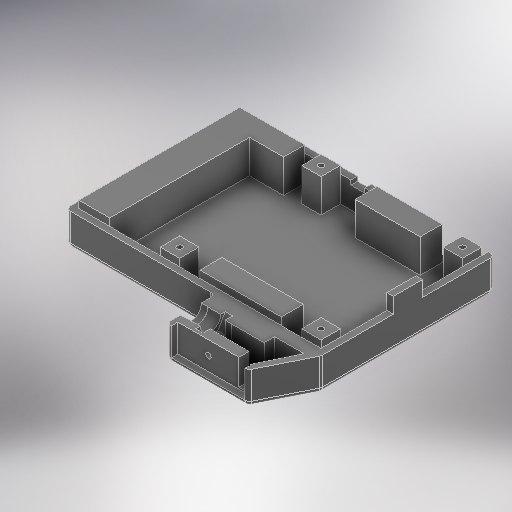
# Autodesk Inventor part: back_casing
Saved by Autodesk Inventor 2027 (Build 310192060, 192F)
## iProperties
Created: 2026-09-11
Part Number: back_casing
Material: Generic
Document SubType Name: Modeling
Designer: Aiden
Density: 1 g/cm^3
Appearance: Smooth - Black
Author: Aiden
Autodesk Inventor part; units mm, degrees
ref_plane "YZ Plane" through (0, 0, 0) normal (1, 0, 0) x (0, 1, 0)
ref_plane "XZ Plane" through (0, 0, 0) normal (0, 1, 0) x (-1, 0, 0)
ref_plane "XY Plane" through (0, 0, 0) normal (0, 0, 1) x (1, 0, 0)
sketch "Sketch1" plane through (0, 0, 0) normal (0, 1, 0) x (-1, 0, 0)
  line L0 (0, 0) -> (54.318, 0)
  line L1 (54.318, 0) -> (54.318, -54.318)
  line L2 (54.318, -54.318) -> (0, -54.318)
  line L3 (0, -54.318) -> (0, 0)
  line L4 (52.286, -52.286) -> (52.286, -54.318) construction
  line L5 (2.032, -2.032) -> (2.032, 0) construction
  line L6 (2.032, -52.286) -> (0, -52.286) construction
  line L7 (54.318, 0) -> (79.718, 0)
  line L8 (79.718, 0) -> (79.718, -54.318)
  line L9 (79.718, -54.318) -> (54.318, -54.318)
  line L10 (54.318, -54.318) -> (54.318, 0)
  dimension "d0" = 54.318
  dimension "d1" = 54.318
  dimension "d8" = 25.4
  constraints: 22 end point, 6 perpendicular, 4 parallel, 3 point on line, 2 horizontal
  measures "d0" distance of L0.end L1.end
  measures "d1" distance of L1.end L2.end
  measures "d8" distance of L8.end L9.end
extrude "Extrusion1" add sketch "Sketch1" along normal blind 10.16
sketch "Sketch3" plane through (0, 10.16, 0) normal (0, 1, 0) x (1, 0, 0)
  line L0 (-77.686, 2.032) -> (-2.032, 2.032)
  line L1 (-2.032, 2.032) -> (-2.032, 52.286)
  line L2 (-2.032, 52.286) -> (-77.686, 52.286)
  line L3 (-77.686, 52.286) -> (-77.686, 2.032)
  line L4 (-77.686, 2.032) -> (-79.718, 2.032) construction
  line L5 (-79.718, 54.318) -> (-79.718, 0) construction
  line L6 (-77.686, 52.286) -> (-77.686, 54.318) construction
  line L7 (-2.032, 52.286) -> (0, 52.286) construction
  line L8 (-2.032, 2.032) -> (-2.032, 0) construction
  line L9 (-79.718, 0) -> (0, 0) construction
  line L10 (0, 54.318) -> (-79.718, 54.318) construction
  line L11 (0, 0) -> (0, 54.318) construction
  dimension "d9" = 2.032
  constraints: 16 end point, 5 perpendicular, 4 point on line, 3 horizontal, 2 parallel, 1 vertical
  measures "d9" distance of L0.start L4.end
extrude "Extrusion3" cut sketch "Sketch3" against normal blind 8.128
sketch "Sketch5" plane through (0, 2.032, 0) normal (0, 1, 0) x (1, 0, 0)
  line L0 (-2.032, 2.032) -> (-77.686, 2.032) projected
  line L1 (-2.032, 2.032) -> (-8.09, 2.032)
  line L2 (-8.09, 2.032) -> (-8.09, 8.09)
  line L3 (-8.09, 8.09) -> (-2.032, 8.09)
  line L4 (-2.032, 8.09) -> (-2.032, 2.032)
  line L5 (-77.686, 52.286) -> (-2.032, 52.286) projected
  line L6 (-2.032, 52.286) -> (-8.09, 52.286)
  line L7 (-8.09, 52.286) -> (-8.09, 46.228)
  line L8 (-8.09, 46.228) -> (-2.032, 46.228)
  line L9 (-2.032, 46.228) -> (-2.032, 52.286)
  line L10 (-52.286, 2.032) -> (-46.228, 2.032)
  line L11 (-46.228, 2.032) -> (-46.228, 8.09)
  line L12 (-46.228, 8.09) -> (-52.286, 8.09)
  line L13 (-52.286, 8.09) -> (-52.286, 2.032)
  line L14 (-52.286, 52.286) -> (-46.228, 52.286)
  line L15 (-46.228, 52.286) -> (-46.228, 46.228)
  line L16 (-46.228, 46.228) -> (-52.286, 46.228)
  line L17 (-52.286, 46.228) -> (-52.286, 52.286)
  line L18 (-52.286, 8.09) -> (-52.286, 46.228) construction
  line L19 (-49.257, 8.09) -> (-49.257, 2.032) construction
  line L20 (-46.228, 5.061) -> (-52.286, 5.061) construction
  line L21 (-49.257, 46.228) -> (-49.257, 52.286) construction
  line L22 (-52.286, 49.257) -> (-46.228, 49.257) construction
  line L23 (-8.09, 49.257) -> (-2.032, 49.257) construction
  line L24 (-5.061, 46.228) -> (-5.061, 52.286) construction
  line L25 (-8.09, 5.061) -> (-2.032, 5.061) construction
  line L26 (-5.061, 8.09) -> (-5.061, 2.032) construction
  circle A0 centre (-49.257, 5.061) radius 0.825
  circle A1 centre (-49.257, 49.257) radius 0.825
  circle A2 centre (-5.061, 49.257) radius 0.825
  circle A3 centre (-5.061, 5.061) radius 0.825
  point P0 (0, 0)
  point P1 (-8.09, 2.032)
  dimension "d12" = 44.196
  dimension "d13" = 44.196
  dimension "d21" = 1.65
  constraints: 50 end point, 23 midpoint, 8 parallel, 7 equal length, 4 centre point, 4 horizontal, 4 perpendicular, 3 equal radius, 2 point on line, 1 collinear
  measures "d12" distance of point (-5.061, 49.257) point (-49.257, 49.257)
  measures "d13" distance of A1.centre point (-49.257, 5.061)
  measures "d21" diameter of A0
extrude "Extrusion4" add sketch "Sketch5" along normal blind 10.414
sketch "Sketch6" plane through (0, 2.032, 0) normal (0, 1, 0) x (1, 0, 0)
  line L0 (-8.09, 2.032) -> (-46.228, 2.032) projected
  line L1 (-39.859, 2.032) -> (-14.459, 2.032)
  line L2 (-14.459, 2.032) -> (-14.459, 8.89)
  line L3 (-14.459, 8.89) -> (-39.859, 8.89)
  line L4 (-39.859, 8.89) -> (-39.859, 2.032)
  line L5 (-46.228, 52.286) -> (-8.09, 52.286) projected
  line L6 (-46.228, 8.09) -> (-46.228, 2.032) construction
  line L7 (-39.859, 8.89) -> (-46.228, 8.09) construction
  line L8 (-8.09, 8.09) -> (-2.032, 8.09) construction
  line L9 (-14.459, 8.89) -> (-8.09, 8.09) construction
  line L10 (-77.686, 2.032) -> (-77.686, 52.286) projected
  line L11 (-77.686, 52.286) -> (-74.1029, 52.286)
  line L12 (-68.034, 45.682) -> (-68.034, 2.032)
  line L13 (-68.034, 2.032) -> (-77.686, 2.032)
  line L14 (-77.686, 2.032) -> (-77.686, 52.286)
  line L15 (-74.1029, 52.286) -> (-57.366, 52.286)
  line L16 (-57.366, 52.286) -> (-57.366, 45.682)
  line L17 (-57.366, 45.682) -> (-68.034, 45.682)
  line L18 (-14.459, 8.89) -> (-14.459, 45.428) construction
  line L19 (-46.228, 52.286) -> (-8.09, 52.286) projected
  line L20 (-14.459, 45.428) -> (-34.779, 45.428)
  line L21 (-34.779, 45.428) -> (-34.779, 52.286)
  line L22 (-34.779, 52.286) -> (-14.459, 52.286)
  line L23 (-14.459, 52.286) -> (-14.459, 45.428)
  point P0 (0, 0)
  point P1 (-39.859, 52.286)
  point P2 (-14.459, 2.032)
  dimension "d16" = 6.858
  dimension "d17" = 25.4
  dimension "d26" = 9.652
  dimension "d27" = 50.254
  dimension "d28" = 6.604
  dimension "d29" = 20.32
  dimension "d67" = 20.32
  constraints: 36 end point, 7 parallel, 4 horizontal, 4 perpendicular, 3 point on line, 2 equal length, 1 vertical
  measures "d16" distance of L3.end L1.start
  measures "d17" distance of L2.end L3.end
  measures "d26" distance of L12.end L13.end
  measures "d27" distance between parallel lines of L11 L13
  measures "d28" distance of L15.end L16.end
  measures "d29" distance between parallel lines of L10 L16
  measures "d67" distance of L18.end L20.end
extrude "Extrusion5" add sketch "Sketch6" along normal blind 10.414
sketch "Sketch7" plane through (0, 10.16, 0) normal (0, 1, 0) x (1, 0, 0)
  line L0 (-46.228, 52.286) -> (-52.286, 52.286) projected
  line L1 (0, 54.318) -> (-79.718, 54.318) projected
  line L2 (-42.926, 52.286) -> (-38.608, 52.286)
  line L3 (-38.608, 52.286) -> (-38.608, 54.318)
  line L4 (-38.608, 54.318) -> (-42.926, 54.318)
  line L5 (-42.926, 54.318) -> (-42.926, 52.286)
  line L6 (0, 0) -> (0, 54.318) projected
  point P0 (-39.859, 52.286)
  dimension "d24" = 4.318
  dimension "d25" = 38.608
  constraints: 8 end point, 2 parallel, 2 point on line, 1 horizontal, 1 perpendicular
  measures "d24" distance between parallel lines of L5 L3
  measures "d25" distance between parallel lines of L6 L3
extrude "Extrusion6" cut sketch "Sketch7" against normal blind 1.397
sketch "Sketch19" plane through (0, 10.16, 0) normal (0, 1, 0) x (1, 0, 0)
  line L0 (0, 52.794) -> (0, 0) construction
  line L1 (0, 0) -> (0, 54.318) projected
  line L2 (-2.032, 22.587) -> (0, 22.587)
  line L3 (0, 22.587) -> (0, 31.731)
  line L4 (0, 31.731) -> (-2.032, 31.731)
  line L5 (-2.032, 31.731) -> (-2.032, 22.587)
  line L6 (-2.032, 46.228) -> (-2.032, 8.09) projected
  point P0 (0, 22.587)
  point P1 (-2.032, 27.159)
  dimension "d74" = 9.144
  constraints: 8 end point, 2 midpoint, 2 parallel, 2 point on line, 1 horizontal, 1 perpendicular
  measures "d74" distance between parallel lines of L2 L4
extrude "Extrusion16" add sketch "Sketch19" along normal blind 4.826
sketch "Sketch21" plane through (0, 10.16, 0) normal (0, 1, 0) x (1, 0, 0)
  line L0 (-78.194, 54.318) -> (-1.524, 54.318) projected
  line L1 (-20.517, 52.286) -> (-2.032, 52.286)
  line L2 (-2.032, 52.286) -> (-2.032, 54.318)
  line L3 (-2.032, 54.318) -> (-20.517, 54.318)
  line L4 (-20.517, 54.318) -> (-20.517, 52.286)
  line L5 (-14.459, 52.286) -> (-8.09, 52.286) projected
  point P0 (-11.2745, 52.286)
  constraints: 8 end point, 2 midpoint, 2 parallel, 1 horizontal, 1 perpendicular
extrude "Extrusion18" cut sketch "Sketch21" against normal blind 8.128
sketch "Sketch24" plane through (0, 0, 0) normal (0, -1, 0) x (1, 0, 0)
  line L0 (0, 0) -> (-7.62, 15.24)
  line L1 (-7.62, 15.24) -> (-33.02, 15.24)
  line L2 (-33.02, 15.24) -> (-33.02, 0)
  line L3 (-33.02, 0) -> (0, 0)
  dimension "d79" = 15.24
  dimension "d80" = 25.4
  dimension "d81" = 7.62
  constraints: 8 end point, 2 perpendicular, 1 horizontal
  measures "d79" distance of L1.end L2.end
  measures "d80" distance of L0.end L1.end
  measures "d81" horizontal distance of L0.end L0.start
extrude "Extrusion20" add sketch "Sketch24" against normal blind 10.16
sketch "Sketch32" plane through (0, 10.16, 0) normal (0, 1, 0) x (1, 0, 0)
  line L0 (-30.988, -13.208) -> (-8.8758, -13.208)
  line L1 (-8.8758, -13.208) -> (-3.2878, -2.032)
  line L2 (-3.2878, -2.032) -> (-30.988, -2.032)
  line L3 (-30.988, -2.032) -> (-30.988, -13.208)
  line L4 (-7.62, -15.24) -> (0, 0) projected
  line L5 (-33.02, 0) -> (-33.02, -15.24) construction
  line L6 (-7.62, -15.24) -> (-33.02, -15.24) construction
  line L7 (0, 0) -> (0, 22.587) construction
  line L8 (-33.02, 0) -> (0, 0) construction
  dimension "d105" = 2.032
  dimension "d106" = 2.032
  dimension "d107" = 2.032
  dimension "d108" = 2.032
  constraints: 10 end point, 2 parallel, 2 perpendicular, 1 horizontal
  measures "d105" distance between parallel lines of L1 L4
  measures "d106" distance between parallel lines of L6 L0
  measures "d107" distance between parallel lines of L5 L3
  measures "d108" distance between parallel lines of L8 L2
extrude "Extrusion27" cut sketch "Sketch32" against normal blind 8.128
sketch "Sketch33" plane through (-33.02, 0, 0) normal (-1, 0, 0) x (0, 0, 1)
  line L0 (2.032, 10.16) -> (13.208, 10.16) projected
  circle A0 centre (7.62, 10.16) radius 3.25
  point P0 (0, 0)
  point P1 (10.87, 10.16)
  point P2 (4.37, 10.16)
  dimension "d111" = 6.5
  constraints: 1 centre point, 1 midpoint
  measures "d111" diameter of A0
extrude "Extrusion28" cut sketch "Sketch33" against normal blind 2.032 contours L0 A0 picked at (8.6107, 9.3973)
fillet "Fillet4" radius 1.524 14 edges at (-79.718, 0, -27.159) (-56.369, 0, 0) (-39.859, 0, -54.318) (-79.718, 5.08, -54.318) (-79.718, 5.08, 0) (-33.02, 5.08, 0) (-33.02, 0, 7.62) (-20.32, 0, 15.24) (-33.02, 5.08, 15.24) (-7.62, 5.08, 15.24) (0, 5.08, 0) (-3.81, 0, 7.62) (0, 0, -27.159) (0, 5.08, -54.318)
sketch "Sketch39" plane through (-30.988, 2.032, 13.208) normal (1, 0, 0) x (0, 0, -1)
  arc A0 (2.338, 8.128) -> (8.838, 8.128) centre (5.588, 8.128) ccw construction
  arc A1 (2.388, 8.128) -> (8.788, 8.128) centre (5.588, 8.128) ccw
  line L0 (0, 8.128) -> (0, 0) projected
  line L1 (0, 8.128) -> (2.388, 8.128)
  line L2 (11.176, 8.128) -> (11.176, 0) projected
  line L3 (0, 0) -> (11.176, 0)
  line L4 (11.176, 0) -> (11.176, 8.128)
  line L5 (11.176, 8.128) -> (12.8862, 8.128) projected
  line L6 (11.176, 8.128) -> (8.788, 8.128)
  point P0 (13.208, -2.032)
  dimension "d117" = 6.4
  constraints: 8 end point, 2 point on circle, 1 centre point, 1 coincident, 1 horizontal, 1 perpendicular, 1 point on line
  measures "d117" diameter of A1
extrude "Extrusion30" add sketch "Sketch39" along normal blind 4.048
sketch "Sketch40" plane through (-26.94, 2.032, 13.208) normal (1, 0, 0) x (0, 0, -1)
  line L0 (0.9692, 8.128) -> (3.2786, 4.128)
  line L1 (3.2786, 4.128) -> (7.8974, 4.128)
  line L2 (7.8974, 4.128) -> (10.2068, 8.128)
  line L3 (0.9692, 8.128) -> (0, 8.128)
  line L4 (0, -0.508) -> (0, 8.128) projected
  line L5 (10.2068, 8.128) -> (11.176, 8.128)
  line L6 (11.176, 8.128) -> (11.176, -0.508) projected
  line L7 (2.388, 8.128) -> (0, 8.128) projected
  line L8 (11.176, 0) -> (0, 0) projected
  line L9 (0, 8.128) -> (0, 0)
  line L10 (0, 0) -> (11.176, 0)
  line L11 (11.176, 8.128) -> (11.176, 0)
  point P0 (13.208, -2.032)
  point P1 (0.4846, 8.128)
  dimension "d120" = 120
  dimension "d121" = 120
  dimension "d123" = 4
  constraints: 16 end point, 5 point on line, 3 equal length, 2 horizontal, 2 perpendicular, 1 collinear, 1 midpoint
  measures "d120" angle of L1 L0
  measures "d121" angle of L2 L1
  measures "d123" distance between parallel lines of L3 L1
extrude "Extrusion31" add sketch "Sketch40" along normal blind 2.286
sketch "Sketch41" plane through (-24.654, 2.032, 13.208) normal (1, 0, 0) x (0, 0, -1)
  line L0 (0, 0) -> (3.2786, 0)
  line L1 (3.2786, 0) -> (3.2786, 8.128)
  line L2 (3.2786, 8.128) -> (0, 8.128)
  line L3 (0, 8.128) -> (0, 0)
  line L4 (11.176, 8.128) -> (11.176, -0.508) projected
  line L5 (11.176, 0) -> (7.8974, 0)
  line L6 (7.8974, 0) -> (7.8974, 8.128)
  line L7 (7.8974, 8.128) -> (11.176, 8.128)
  line L8 (11.176, 8.128) -> (11.176, 0)
  point P0 (13.208, -2.032)
  constraints: 16 end point, 4 parallel, 3 point on line, 2 horizontal, 2 perpendicular
extrude "Extrusion32" add sketch "Sketch41" along normal blind 2.032
sketch "Sketch42" plane through (-22.622, 2.032, 13.208) normal (1, 0, 0) x (0, 0, -1)
  line L0 (3.2786, 0) -> (3.2786, 8.128) projected
  line L1 (3.2786, 0) -> (0, 0) projected
  line L2 (3.2786, 8.128) -> (0, 8.128)
  line L3 (0, 8.128) -> (0, 0)
  line L4 (0, 0) -> (3.2786, 0)
  line L5 (3.2786, 0) -> (3.2786, 8.128)
  line L6 (11.176, 8.128) -> (11.176, -0.508) projected
  line L7 (7.8848, 0) -> (11.176, 0)
  line L8 (11.176, 0) -> (11.176, 8.128)
  line L9 (11.176, 8.128) -> (7.8848, 8.128)
  line L10 (7.8848, 8.128) -> (7.8848, 0)
  point P0 (13.208, -2.032)
  constraints: 16 end point, 4 parallel, 2 horizontal, 2 perpendicular, 1 point on line
extrude "Extrusion33" add sketch "Sketch42" along normal blind 10.16
sketch "Sketch43" plane through (-31.496, 10.16, 15.24) normal (0, 0, 1) x (1, 0, 0)
  line L0 (0, -8.636) -> (0, 0) projected
  line L1 (22.9341, 0) -> (22.9341, -8.636) projected
  line L2 (0, -8.636) -> (22.9341, -8.636)
  line L3 (22.9341, -8.636) -> (22.9341, 0)
  line L4 (22.9341, 0) -> (0, 0)
  line L5 (0, 0) -> (0, -8.636)
  point P0 (31.496, -10.16)
  constraints: 8 end point, 2 parallel, 1 horizontal, 1 perpendicular
extrude "Extrusion34" cut sketch "Sketch43" against normal blind 2.032
sketch "Sketch44" plane through (-31.496, 10.16, 13.208) normal (0, 0, 1) x (1, 0, 0)
  circle A0 centre (9.517, -4.318) radius 0.825
  line L0 (0, -8.636) -> (0, 0) construction
  line L1 (0, -4.318) -> (19.034, -4.318) construction
  line L2 (19.034, -8.128) -> (19.034, 0) construction
  point P0 (31.496, -10.16)
  dimension "d132" = 1.65
  constraints: 2 end point, 2 midpoint, 1 centre point, 1 coincident, 1 horizontal, 1 point on line
  measures "d132" diameter of A0
extrude "Extrusion35" cut sketch "Sketch44" against normal blind 5.08
body "Solid1"
